Autodesk Fusion 360 part; units mm, degrees
(part 3 of 3)
sketch "Sketch14" plane through (608, 0, 0) normal (1, 0, 0) x (0, 0, -1) in component "ДСП 16 — ламель прямая 982х100х16 мм — 8 шт"
  line L0 (-270, 982) -> (-295, 982) construction
  line L1 (-295, 982) -> (-295, 0) construction
  line L2 (-295, 0) -> (-245, 0) construction
  line L3 (-245, 0) -> (-245, 16) construction
  line L4 (-245, 16) -> (-195, 16) construction
  line L5 (-195, 16) -> (-195, 245.5) construction
  line L6 (-195, 245.5) -> (-245, 245.5) construction
  line L7 (-245, 245.5) -> (-245, 261.5) construction
  line L8 (-245, 261.5) -> (-195, 261.5) construction
  line L9 (-195, 261.5) -> (-195, 491) construction
  line L10 (-195, 491) -> (-245, 491) construction
  line L11 (-245, 491) -> (-245, 507) construction
  line L12 (-245, 507) -> (-195, 507) construction
  line L13 (-195, 507) -> (-195, 736.5) construction
  line L14 (-195, 736.5) -> (-245, 736.5) construction
  line L15 (-245, 736.5) -> (-245, 752.5) construction
  line L16 (-245, 752.5) -> (-195, 752.5) construction
  line L17 (-195, 752.5) -> (-195, 850) construction
  line L18 (-195, 850) -> (-270, 850) construction
  line L19 (-270, 850) -> (-270, 982) construction
  line L20 (-245, -0.1) -> (-193, -0.1)
  line L21 (-193, -0.1) -> (-193, 16.1)
  line L22 (-193, 16.1) -> (-245, 16.1)
  line L23 (-245, 16.1) -> (-245, -0.1)
  line L24 (-245, 245.4) -> (-193, 245.4)
  line L25 (-193, 245.4) -> (-193, 261.6)
  line L26 (-193, 261.6) -> (-245, 261.6)
  line L27 (-245, 261.6) -> (-245, 245.4)
  line L28 (-245, 490.9) -> (-193, 490.9)
  line L29 (-193, 490.9) -> (-193, 507.1)
  line L30 (-193, 507.1) -> (-245, 507.1)
  line L31 (-245, 507.1) -> (-245, 490.9)
  line L32 (-245, 736.4) -> (-193, 736.4)
  line L33 (-193, 736.4) -> (-193, 752.6)
  line L34 (-193, 752.6) -> (-245, 752.6)
  line L35 (-245, 752.6) -> (-245, 736.4)
extrude "Зазор паза +0,2 мм Тело 12" cut sketch "Sketch14" along normal mid plane 80 bodies 45 in component "ДСП 16 — ламель прямая 982х100х16 мм — 8 шт"
sketch "Sketch15" plane through (592, 0, 0) normal (-1, 0, 0) x (0, 0, 1) in component "ДСП 16 — ламель прямая 982х100х16 мм — 8 шт"
  line L0 (195, 507.1) -> (245, 507.1) construction
  line L1 (245, 507.1) -> (245, 490.9) construction
  line L2 (245, 490.9) -> (195, 490.9) construction
  line L3 (195, 490.9) -> (195, 261.6) construction
  line L4 (195, 261.6) -> (245, 261.6) construction
  line L5 (245, 261.6) -> (245, 245.4) construction
  line L6 (245, 245.4) -> (195, 245.4) construction
  line L7 (195, 245.4) -> (195, 16.1) construction
  line L8 (195, 16.1) -> (245, 16.1) construction
  line L9 (245, 16.1) -> (245, 0) construction
  line L10 (245, 0) -> (295, 0) construction
  line L11 (295, 0) -> (295, 982) construction
  line L12 (295, 982) -> (270, 982) construction
  line L13 (270, 982) -> (270, 850) construction
  line L14 (270, 850) -> (195, 850) construction
  line L15 (195, 850) -> (195, 752.6) construction
  line L16 (195, 752.6) -> (245, 752.6) construction
  line L17 (245, 752.6) -> (245, 736.4) construction
  line L18 (245, 736.4) -> (195, 736.4) construction
  line L19 (195, 736.4) -> (195, 507.1) construction
  circle A0 centre (243.5151, 14.6151) radius 2.1
  circle A1 centre (243.5151, 246.8849) radius 2.1
  circle A2 centre (243.5151, 260.1151) radius 2.1
  circle A3 centre (243.5151, 492.3849) radius 2.1
  circle A4 centre (243.5151, 505.6151) radius 2.1
  circle A5 centre (243.5151, 737.8849) radius 2.1
  circle A6 centre (243.5151, 751.1151) radius 2.1
extrude "Догбон Ø4,2 мм Тело 12" cut sketch "Sketch15" along normal mid plane 80 bodies 45 in component "ДСП 16 — ламель прямая 982х100х16 мм — 8 шт"
sketch "Sketch16" plane through (808, 0, 0) normal (1, 0, 0) x (0, 0, -1) in component "ДСП 16 — ламель прямая 982х100х16 мм — 8 шт"
  line L0 (-270, 982) -> (-295, 982) construction
  line L1 (-295, 982) -> (-295, 0) construction
  line L2 (-295, 0) -> (-245, 0) construction
  line L3 (-245, 0) -> (-245, 16) construction
  line L4 (-245, 16) -> (-195, 16) construction
  line L5 (-195, 16) -> (-195, 245.5) construction
  line L6 (-195, 245.5) -> (-245, 245.5) construction
  line L7 (-245, 245.5) -> (-245, 261.5) construction
  line L8 (-245, 261.5) -> (-195, 261.5) construction
  line L9 (-195, 261.5) -> (-195, 491) construction
  line L10 (-195, 491) -> (-245, 491) construction
  line L11 (-245, 491) -> (-245, 507) construction
  line L12 (-245, 507) -> (-195, 507) construction
  line L13 (-195, 507) -> (-195, 736.5) construction
  line L14 (-195, 736.5) -> (-245, 736.5) construction
  line L15 (-245, 736.5) -> (-245, 752.5) construction
  line L16 (-245, 752.5) -> (-195, 752.5) construction
  line L17 (-195, 752.5) -> (-195, 850) construction
  line L18 (-195, 850) -> (-270, 850) construction
  line L19 (-270, 850) -> (-270, 982) construction
  line L20 (-245, -0.1) -> (-193, -0.1)
  line L21 (-193, -0.1) -> (-193, 16.1)
  line L22 (-193, 16.1) -> (-245, 16.1)
  line L23 (-245, 16.1) -> (-245, -0.1)
  line L24 (-245, 245.4) -> (-193, 245.4)
  line L25 (-193, 245.4) -> (-193, 261.6)
  line L26 (-193, 261.6) -> (-245, 261.6)
  line L27 (-245, 261.6) -> (-245, 245.4)
  line L28 (-245, 490.9) -> (-193, 490.9)
  line L29 (-193, 490.9) -> (-193, 507.1)
  line L30 (-193, 507.1) -> (-245, 507.1)
  line L31 (-245, 507.1) -> (-245, 490.9)
  line L32 (-245, 736.4) -> (-193, 736.4)
  line L33 (-193, 736.4) -> (-193, 752.6)
  line L34 (-193, 752.6) -> (-245, 752.6)
  line L35 (-245, 752.6) -> (-245, 736.4)
extrude "Зазор паза +0,2 мм Тело 14" cut sketch "Sketch16" along normal mid plane 80 bodies 47 in component "ДСП 16 — ламель прямая 982х100х16 мм — 8 шт"
sketch "Sketch17" plane through (792, 0, 0) normal (-1, 0, 0) x (0, 0, 1) in component "ДСП 16 — ламель прямая 982х100х16 мм — 8 шт"
  line L0 (195, 507.1) -> (245, 507.1) construction
  line L1 (245, 507.1) -> (245, 490.9) construction
  line L2 (245, 490.9) -> (195, 490.9) construction
  line L3 (195, 490.9) -> (195, 261.6) construction
  line L4 (195, 261.6) -> (245, 261.6) construction
  line L5 (245, 261.6) -> (245, 245.4) construction
  line L6 (245, 245.4) -> (195, 245.4) construction
  line L7 (195, 245.4) -> (195, 16.1) construction
  line L8 (195, 16.1) -> (245, 16.1) construction
  line L9 (245, 16.1) -> (245, 0) construction
  line L10 (245, 0) -> (295, 0) construction
  line L11 (295, 0) -> (295, 982) construction
  line L12 (295, 982) -> (270, 982) construction
  line L13 (270, 982) -> (270, 850) construction
  line L14 (270, 850) -> (195, 850) construction
  line L15 (195, 850) -> (195, 752.6) construction
  line L16 (195, 752.6) -> (245, 752.6) construction
  line L17 (245, 752.6) -> (245, 736.4) construction
  line L18 (245, 736.4) -> (195, 736.4) construction
  line L19 (195, 736.4) -> (195, 507.1) construction
  circle A0 centre (243.5151, 14.6151) radius 2.1
  circle A1 centre (243.5151, 246.8849) radius 2.1
  circle A2 centre (243.5151, 260.1151) radius 2.1
  circle A3 centre (243.5151, 492.3849) radius 2.1
  circle A4 centre (243.5151, 505.6151) radius 2.1
  circle A5 centre (243.5151, 737.8849) radius 2.1
  circle A6 centre (243.5151, 751.1151) radius 2.1
extrude "Догбон Ø4,2 мм Тело 14" cut sketch "Sketch17" along normal mid plane 80 bodies 47 in component "ДСП 16 — ламель прямая 982х100х16 мм — 8 шт"
sketch "Sketch2 (28)" plane through (695.5237, 0, 401.5608) normal (-0.866025, 0, -0.5) x (-0.5, 0, 0.866025) in component "ДСП 16 — ламель радиусная 982х100х16 мм — 6 шт"
  line L0 (-415.0962, 982) -> (-439.8753, 982) construction
  line L1 (-439.8753, 982) -> (-439.8753, 0) construction
  line L2 (-439.8753, 0) -> (-390.0962, 0) construction
  line L3 (-390.0962, 0) -> (-390.0962, 16) construction
  line L4 (-390.0962, 16) -> (-340.0962, 16) construction
  line L5 (-340.0962, 16) -> (-340.0962, 245.5) construction
  line L6 (-340.0962, 245.5) -> (-390.0962, 245.5) construction
  line L7 (-390.0962, 245.5) -> (-390.0962, 261.5) construction
  line L8 (-390.0962, 261.5) -> (-340.0962, 261.5) construction
  line L9 (-340.0962, 261.5) -> (-340.0962, 491) construction
  line L10 (-340.0962, 491) -> (-390.0962, 491) construction
  line L11 (-390.0962, 491) -> (-390.0962, 507) construction
  line L12 (-390.0962, 507) -> (-340.0962, 507) construction
  line L13 (-340.0962, 507) -> (-340.0962, 736.5) construction
  line L14 (-340.0962, 736.5) -> (-390.0962, 736.5) construction
  line L15 (-390.0962, 736.5) -> (-390.0962, 752.5) construction
  line L16 (-390.0962, 752.5) -> (-340.0962, 752.5) construction
  line L17 (-340.0962, 752.5) -> (-340.0962, 850) construction
  line L18 (-340.0962, 850) -> (-415.0962, 850) construction
  line L19 (-415.0962, 850) -> (-415.0962, 982) construction
  line L20 (-390.0962, -0.1) -> (-338.0962, -0.1)
  line L21 (-338.0962, -0.1) -> (-338.0962, 16.1)
  line L22 (-338.0962, 16.1) -> (-390.0962, 16.1)
  line L23 (-390.0962, 16.1) -> (-390.0962, -0.1)
  line L24 (-390.0962, 245.4) -> (-338.0962, 245.4)
  line L25 (-338.0962, 245.4) -> (-338.0962, 261.6)
  line L26 (-338.0962, 261.6) -> (-390.0962, 261.6)
  line L27 (-390.0962, 261.6) -> (-390.0962, 245.4)
  line L28 (-390.0962, 490.9) -> (-338.0962, 490.9)
  line L29 (-338.0962, 490.9) -> (-338.0962, 507.1)
  line L30 (-338.0962, 507.1) -> (-390.0962, 507.1)
  line L31 (-390.0962, 507.1) -> (-390.0962, 490.9)
  line L32 (-390.0962, 736.4) -> (-338.0962, 736.4)
  line L33 (-338.0962, 736.4) -> (-338.0962, 752.6)
  line L34 (-338.0962, 752.6) -> (-390.0962, 752.6)
  line L35 (-390.0962, 752.6) -> (-390.0962, 736.4)
extrude "Зазор паза +0,2 мм Тело 01'" cut sketch "Sketch2 (28)" along normal mid plane 80 bodies 48 in component "ДСП 16 — ламель радиусная 982х100х16 мм — 6 шт"
sketch "Sketch3 (8)" plane through (709.3801, 0, 409.5608) normal (0.866025, 0, 0.5) x (0.5, 0, -0.866025) in component "ДСП 16 — ламель радиусная 982х100х16 мм — 6 шт"
  line L0 (340.0962, 507.1) -> (390.0962, 507.1) construction
  line L1 (390.0962, 507.1) -> (390.0962, 490.9) construction
  line L2 (390.0962, 490.9) -> (340.0962, 490.9) construction
  line L3 (340.0962, 490.9) -> (340.0962, 261.6) construction
  line L4 (340.0962, 261.6) -> (390.0962, 261.6) construction
  line L5 (390.0962, 261.6) -> (390.0962, 245.4) construction
  line L6 (390.0962, 245.4) -> (340.0962, 245.4) construction
  line L7 (340.0962, 245.4) -> (340.0962, 16.1) construction
  line L8 (340.0962, 16.1) -> (390.0962, 16.1) construction
  line L9 (390.0962, 16.1) -> (390.0962, 0) construction
  line L10 (390.0962, 0) -> (439.8753, 0) construction
  line L11 (439.8753, 0) -> (439.8753, 982) construction
  line L12 (439.8753, 982) -> (415.0962, 982) construction
  line L13 (415.0962, 982) -> (415.0962, 850) construction
  line L14 (415.0962, 850) -> (340.0962, 850) construction
  line L15 (340.0962, 850) -> (340.0962, 752.6) construction
  line L16 (340.0962, 752.6) -> (390.0962, 752.6) construction
  line L17 (390.0962, 752.6) -> (390.0962, 736.4) construction
  line L18 (390.0962, 736.4) -> (340.0962, 736.4) construction
  line L19 (340.0962, 736.4) -> (340.0962, 507.1) construction
  circle A0 centre (388.6113, 14.6151) radius 2.1
  circle A1 centre (388.6113, 246.8849) radius 2.1
  circle A2 centre (388.6113, 260.1151) radius 2.1
  circle A3 centre (388.6113, 492.3849) radius 2.1
  circle A4 centre (388.6113, 505.6151) radius 2.1
  circle A5 centre (388.6113, 737.8849) radius 2.1
  circle A6 centre (388.6113, 751.1151) radius 2.1
extrude "Догбон Ø4,2 мм Тело 01'" cut sketch "Sketch3 (8)" along normal mid plane 80 bodies 48 in component "ДСП 16 — ламель радиусная 982х100х16 мм — 6 шт"
sketch "Sketch4 (2)" plane through (0, 0, 142) normal (0, 0, -1) x (-1, 0, 0) in component "ДСП 16 — ламель радиусная 982х100х16 мм — 6 шт"
  line L0 (-970, 982) -> (-994.7791, 982) construction
  line L1 (-994.7791, 982) -> (-994.7791, 0) construction
  line L2 (-994.7791, 0) -> (-945, 0) construction
  line L3 (-945, 0) -> (-945, 16) construction
  line L4 (-945, 16) -> (-895, 16) construction
  line L5 (-895, 16) -> (-895, 245.5) construction
  line L6 (-895, 245.5) -> (-945, 245.5) construction
  line L7 (-945, 245.5) -> (-945, 261.5) construction
  line L8 (-945, 261.5) -> (-895, 261.5) construction
  line L9 (-895, 261.5) -> (-895, 491) construction
  line L10 (-895, 491) -> (-945, 491) construction
  line L11 (-945, 491) -> (-945, 507) construction
  line L12 (-945, 507) -> (-895, 507) construction
  line L13 (-895, 507) -> (-895, 736.5) construction
  line L14 (-895, 736.5) -> (-945, 736.5) construction
  line L15 (-945, 736.5) -> (-945, 752.5) construction
  line L16 (-945, 752.5) -> (-895, 752.5) construction
  line L17 (-895, 752.5) -> (-895, 850) construction
  line L18 (-895, 850) -> (-970, 850) construction
  line L19 (-970, 850) -> (-970, 982) construction
  line L20 (-945, -0.1) -> (-893, -0.1)
  line L21 (-893, -0.1) -> (-893, 16.1)
  line L22 (-893, 16.1) -> (-945, 16.1)
  line L23 (-945, 16.1) -> (-945, -0.1)
  line L24 (-945, 245.4) -> (-893, 245.4)
  line L25 (-893, 245.4) -> (-893, 261.6)
  line L26 (-893, 261.6) -> (-945, 261.6)
  line L27 (-945, 261.6) -> (-945, 245.4)
  line L28 (-945, 490.9) -> (-893, 490.9)
  line L29 (-893, 490.9) -> (-893, 507.1)
  line L30 (-893, 507.1) -> (-945, 507.1)
  line L31 (-945, 507.1) -> (-945, 490.9)
  line L32 (-945, 736.4) -> (-893, 736.4)
  line L33 (-893, 736.4) -> (-893, 752.6)
  line L34 (-893, 752.6) -> (-945, 752.6)
  line L35 (-945, 752.6) -> (-945, 736.4)
extrude "Зазор паза +0,2 мм Тело 02" cut sketch "Sketch4 (2)" along normal mid plane 80 bodies 49 in component "ДСП 16 — ламель радиусная 982х100х16 мм — 6 шт"
sketch "Sketch5 (2)" plane through (0, 0, 158) normal (0, 0, 1) x (1, 0, 0) in component "ДСП 16 — ламель радиусная 982х100х16 мм — 6 шт"
  line L0 (895, 507.1) -> (945, 507.1) construction
  line L1 (945, 507.1) -> (945, 490.9) construction
  line L2 (945, 490.9) -> (895, 490.9) construction
  line L3 (895, 490.9) -> (895, 261.6) construction
  line L4 (895, 261.6) -> (945, 261.6) construction
  line L5 (945, 261.6) -> (945, 245.4) construction
  line L6 (945, 245.4) -> (895, 245.4) construction
  line L7 (895, 245.4) -> (895, 16.1) construction
  line L8 (895, 16.1) -> (945, 16.1) construction
  line L9 (945, 16.1) -> (945, 0) construction
  line L10 (945, 0) -> (994.7791, 0) construction
  line L11 (994.7791, 0) -> (994.7791, 982) construction
  line L12 (994.7791, 982) -> (970, 982) construction
  line L13 (970, 982) -> (970, 850) construction
  line L14 (970, 850) -> (895, 850) construction
  line L15 (895, 850) -> (895, 752.6) construction
  line L16 (895, 752.6) -> (945, 752.6) construction
  line L17 (945, 752.6) -> (945, 736.4) construction
  line L18 (945, 736.4) -> (895, 736.4) construction
  line L19 (895, 736.4) -> (895, 507.1) construction
  circle A0 centre (943.5151, 14.6151) radius 2.1
  circle A1 centre (943.5151, 246.8849) radius 2.1
  circle A2 centre (943.5151, 260.1151) radius 2.1
  circle A3 centre (943.5151, 492.3849) radius 2.1
  circle A4 centre (943.5151, 505.6151) radius 2.1
  circle A5 centre (943.5151, 737.8849) radius 2.1
  circle A6 centre (943.5151, 751.1151) radius 2.1
extrude "Догбон Ø4,2 мм Тело 02" cut sketch "Sketch5 (2)" along normal mid plane 80 bodies 49 in component "ДСП 16 — ламель радиусная 982х100х16 мм — 6 шт"
sketch "Sketch6 (2)" plane through (565.6199, 0, -326.5608) normal (-0.866025, 0, 0.5) x (0.5, 0, 0.866025) in component "ДСП 16 — ламель радиусная 982х100х16 мм — 6 шт"
  line L0 (699.683, 982) -> (674.9038, 982) construction
  line L1 (674.9038, 982) -> (674.9038, 850) construction
  line L2 (674.9038, 850) -> (599.9038, 850) construction
  line L3 (599.9038, 850) -> (599.9038, 752.5) construction
  line L4 (599.9038, 752.5) -> (649.9038, 752.5) construction
  line L5 (649.9038, 752.5) -> (649.9038, 736.5) construction
  line L6 (649.9038, 736.5) -> (599.9038, 736.5) construction
  line L7 (599.9038, 736.5) -> (599.9038, 507) construction
  line L8 (599.9038, 507) -> (649.9038, 507) construction
  line L9 (649.9038, 507) -> (649.9038, 491) construction
  line L10 (649.9038, 491) -> (599.9038, 491) construction
  line L11 (599.9038, 491) -> (599.9038, 261.5) construction
  line L12 (599.9038, 261.5) -> (649.9038, 261.5) construction
  line L13 (649.9038, 261.5) -> (649.9038, 245.5) construction
  line L14 (649.9038, 245.5) -> (599.9038, 245.5) construction
  line L15 (599.9038, 245.5) -> (599.9038, 16) construction
  line L16 (599.9038, 16) -> (649.9038, 16) construction
  line L17 (649.9038, 16) -> (649.9038, 0) construction
  line L18 (649.9038, 0) -> (699.683, 0) construction
  line L19 (699.683, 0) -> (699.683, 982) construction
  line L20 (649.9038, -0.1) -> (597.9038, -0.1)
  line L21 (597.9038, -0.1) -> (597.9038, 16.1)
  line L22 (597.9038, 16.1) -> (649.9038, 16.1)
  line L23 (649.9038, 16.1) -> (649.9038, -0.1)
  line L24 (649.9038, 245.4) -> (597.9038, 245.4)
  line L25 (597.9038, 245.4) -> (597.9038, 261.6)
  line L26 (597.9038, 261.6) -> (649.9038, 261.6)
  line L27 (649.9038, 261.6) -> (649.9038, 245.4)
  line L28 (649.9038, 490.9) -> (597.9038, 490.9)
  line L29 (597.9038, 490.9) -> (597.9038, 507.1)
  line L30 (597.9038, 507.1) -> (649.9038, 507.1)
  line L31 (649.9038, 507.1) -> (649.9038, 490.9)
  line L32 (649.9038, 736.4) -> (597.9038, 736.4)
  line L33 (597.9038, 736.4) -> (597.9038, 752.6)
  line L34 (597.9038, 752.6) -> (649.9038, 752.6)
  line L35 (649.9038, 752.6) -> (649.9038, 736.4)
extrude "Зазор паза +0,2 мм Тело 03'" cut sketch "Sketch6 (2)" along normal mid plane 80 bodies 50 in component "ДСП 16 — ламель радиусная 982х100х16 мм — 6 шт"
sketch "Sketch7 (2)" plane through (579.4763, 0, -334.5608) normal (0.866025, 0, -0.5) x (-0.5, 0, -0.866025) in component "ДСП 16 — ламель радиусная 982х100х16 мм — 6 шт"
  line L0 (-599.9038, 490.9) -> (-649.9038, 490.9) construction
  line L1 (-649.9038, 490.9) -> (-649.9038, 507.1) construction
  line L2 (-649.9038, 507.1) -> (-599.9038, 507.1) construction
  line L3 (-599.9038, 507.1) -> (-599.9038, 736.4) construction
  line L4 (-599.9038, 736.4) -> (-649.9038, 736.4) construction
  line L5 (-649.9038, 736.4) -> (-649.9038, 752.6) construction
  line L6 (-649.9038, 752.6) -> (-599.9038, 752.6) construction
  line L7 (-599.9038, 752.6) -> (-599.9038, 850) construction
  line L8 (-599.9038, 850) -> (-674.9038, 850) construction
  line L9 (-674.9038, 850) -> (-674.9038, 982) construction
  line L10 (-674.9038, 982) -> (-699.683, 982) construction
  line L11 (-699.683, 982) -> (-699.683, 0) construction
  line L12 (-699.683, 0) -> (-649.9038, 0) construction
  line L13 (-649.9038, 0) -> (-649.9038, 16.1) construction
  line L14 (-649.9038, 16.1) -> (-599.9038, 16.1) construction
  line L15 (-599.9038, 16.1) -> (-599.9038, 245.4) construction
  line L16 (-599.9038, 245.4) -> (-649.9038, 245.4) construction
  line L17 (-649.9038, 245.4) -> (-649.9038, 261.6) construction
  line L18 (-649.9038, 261.6) -> (-599.9038, 261.6) construction
  line L19 (-599.9038, 261.6) -> (-599.9038, 490.9) construction
  circle A0 centre (-648.4189, 14.6151) radius 2.1
  circle A1 centre (-648.4189, 246.8849) radius 2.1
  circle A2 centre (-648.4189, 260.1151) radius 2.1
  circle A3 centre (-648.4189, 492.3849) radius 2.1
  circle A4 centre (-648.4189, 505.6151) radius 2.1
  circle A5 centre (-648.4189, 737.8849) radius 2.1
  circle A6 centre (-648.4189, 751.1151) radius 2.1
extrude "Догбон Ø4,2 мм Тело 03'" cut sketch "Sketch7 (2)" along normal mid plane 80 bodies 50 in component "ДСП 16 — ламель радиусная 982х100х16 мм — 6 шт"
sketch "Sketch8 (2)" plane through (170.5237, 0, 98.4519) normal (-0.866025, 0, -0.5) x (-0.5, 0, 0.866025) in component "ДСП 16 — ламель радиусная 982х100х16 мм — 6 шт"
  line L0 (199.683, 982) -> (174.9038, 982) construction
  line L1 (174.9038, 982) -> (174.9038, 850) construction
  line L2 (174.9038, 850) -> (99.9038, 850) construction
  line L3 (99.9038, 850) -> (99.9038, 752.5) construction
  line L4 (99.9038, 752.5) -> (149.9038, 752.5) construction
  line L5 (149.9038, 752.5) -> (149.9038, 736.5) construction
  line L6 (149.9038, 736.5) -> (99.9038, 736.5) construction
  line L7 (99.9038, 736.5) -> (99.9038, 507) construction
  line L8 (99.9038, 507) -> (149.9038, 507) construction
  line L9 (149.9038, 507) -> (149.9038, 491) construction
  line L10 (149.9038, 491) -> (99.9038, 491) construction
  line L11 (99.9038, 491) -> (99.9038, 261.5) construction
  line L12 (99.9038, 261.5) -> (149.9038, 261.5) construction
  line L13 (149.9038, 261.5) -> (149.9038, 245.5) construction
  line L14 (149.9038, 245.5) -> (99.9038, 245.5) construction
  line L15 (99.9038, 245.5) -> (99.9038, 16) construction
  line L16 (99.9038, 16) -> (149.9038, 16) construction
  line L17 (149.9038, 16) -> (149.9038, 0) construction
  line L18 (149.9038, 0) -> (199.683, 0) construction
  line L19 (199.683, 0) -> (199.683, 982) construction
  line L20 (149.9038, -0.1) -> (97.9038, -0.1)
  line L21 (97.9038, -0.1) -> (97.9038, 16.1)
  line L22 (97.9038, 16.1) -> (149.9038, 16.1)
  line L23 (149.9038, 16.1) -> (149.9038, -0.1)
  line L24 (149.9038, 245.4) -> (97.9038, 245.4)
  line L25 (97.9038, 245.4) -> (97.9038, 261.6)
  line L26 (97.9038, 261.6) -> (149.9038, 261.6)
  line L27 (149.9038, 261.6) -> (149.9038, 245.4)
  line L28 (149.9038, 490.9) -> (97.9038, 490.9)
  line L29 (97.9038, 490.9) -> (97.9038, 507.1)
  line L30 (97.9038, 507.1) -> (149.9038, 507.1)
  line L31 (149.9038, 507.1) -> (149.9038, 490.9)
  line L32 (149.9038, 736.4) -> (97.9038, 736.4)
  line L33 (97.9038, 736.4) -> (97.9038, 752.6)
  line L34 (97.9038, 752.6) -> (149.9038, 752.6)
  line L35 (149.9038, 752.6) -> (149.9038, 736.4)
extrude "Зазор паза +0,2 мм Тело 04" cut sketch "Sketch8 (2)" along normal mid plane 80 bodies 51 in component "ДСП 16 — ламель радиусная 982х100х16 мм — 6 шт"
sketch "Sketch9 (2)" plane through (170.5237, 0, 98.4519) normal (-0.866025, 0, -0.5) x (-0.5, 0, 0.866025) in component "ДСП 16 — ламель радиусная 982х100х16 мм — 6 шт"
  line L0 (149.9038, 490.9) -> (99.9038, 490.9) construction
  line L1 (99.9038, 490.9) -> (99.9038, 261.6) construction
  line L2 (99.9038, 261.6) -> (149.9038, 261.6) construction
  line L3 (149.9038, 261.6) -> (149.9038, 245.4) construction
  line L4 (149.9038, 245.4) -> (99.9038, 245.4) construction
  line L5 (99.9038, 245.4) -> (99.9038, 16.1) construction
  line L6 (99.9038, 16.1) -> (149.9038, 16.1) construction
  line L7 (149.9038, 16.1) -> (149.9038, 0) construction
  line L8 (149.9038, 0) -> (199.683, 0) construction
  line L9 (199.683, 0) -> (199.683, 982) construction
  line L10 (199.683, 982) -> (174.9038, 982) construction
  line L11 (174.9038, 982) -> (174.9038, 850) construction
  line L12 (174.9038, 850) -> (99.9038, 850) construction
  line L13 (99.9038, 850) -> (99.9038, 752.6) construction
  line L14 (99.9038, 752.6) -> (149.9038, 752.6) construction
  line L15 (149.9038, 752.6) -> (149.9038, 736.4) construction
  line L16 (149.9038, 736.4) -> (99.9038, 736.4) construction
  line L17 (99.9038, 736.4) -> (99.9038, 507.1) construction
  line L18 (99.9038, 507.1) -> (149.9038, 507.1) construction
  line L19 (149.9038, 507.1) -> (149.9038, 490.9) construction
  circle A0 centre (148.4189, 14.6151) radius 2.1
  circle A1 centre (148.4189, 246.8849) radius 2.1
  circle A2 centre (148.4189, 260.1151) radius 2.1
  circle A3 centre (148.4189, 492.3849) radius 2.1
  circle A4 centre (148.4189, 505.6151) radius 2.1
  circle A5 centre (148.4189, 737.8849) radius 2.1
  circle A6 centre (148.4189, 751.1151) radius 2.1
extrude "Догбон Ø4,2 мм Тело 04" cut sketch "Sketch9 (2)" along normal mid plane 80 bodies 51 in component "ДСП 16 — ламель радиусная 982х100х16 мм — 6 шт"
sketch "Sketch10 (2)" plane through (0, 0, 158) normal (0, 0, 1) x (1, 0, 0) in component "ДСП 16 — ламель радиусная 982х100х16 мм — 6 шт"
  line L0 (30, 982) -> (5.2209, 982) construction
  line L1 (5.2209, 982) -> (5.2209, 0) construction
  line L2 (5.2209, 0) -> (55, 0) construction
  line L3 (55, 0) -> (55, 16) construction
  line L4 (55, 16) -> (105, 16) construction
  line L5 (105, 16) -> (105, 245.5) construction
  line L6 (105, 245.5) -> (55, 245.5) construction
  line L7 (55, 245.5) -> (55, 261.5) construction
  line L8 (55, 261.5) -> (105, 261.5) construction
  line L9 (105, 261.5) -> (105, 491) construction
  line L10 (105, 491) -> (55, 491) construction
  line L11 (55, 491) -> (55, 507) construction
  line L12 (55, 507) -> (105, 507) construction
  line L13 (105, 507) -> (105, 736.5) construction
  line L14 (105, 736.5) -> (55, 736.5) construction
  line L15 (55, 736.5) -> (55, 752.5) construction
  line L16 (55, 752.5) -> (105, 752.5) construction
  line L17 (105, 752.5) -> (105, 850) construction
  line L18 (105, 850) -> (30, 850) construction
  line L19 (30, 850) -> (30, 982) construction
  line L20 (55, -0.1) -> (107, -0.1)
  line L21 (107, -0.1) -> (107, 16.1)
  line L22 (107, 16.1) -> (55, 16.1)
  line L23 (55, 16.1) -> (55, -0.1)
  line L24 (55, 245.4) -> (107, 245.4)
  line L25 (107, 245.4) -> (107, 261.6)
  line L26 (107, 261.6) -> (55, 261.6)
  line L27 (55, 261.6) -> (55, 245.4)
  line L28 (55, 490.9) -> (107, 490.9)
  line L29 (107, 490.9) -> (107, 507.1)
  line L30 (107, 507.1) -> (55, 507.1)
  line L31 (55, 507.1) -> (55, 490.9)
  line L32 (55, 736.4) -> (107, 736.4)
  line L33 (107, 736.4) -> (107, 752.6)
  line L34 (107, 752.6) -> (55, 752.6)
  line L35 (55, 752.6) -> (55, 736.4)
extrude "Зазор паза +0,2 мм Тело 05'" cut sketch "Sketch10 (2)" along normal mid plane 80 bodies 52 in component "ДСП 16 — ламель радиусная 982х100х16 мм — 6 шт"
sketch "Sketch11 (2)" plane through (0, 0, 158) normal (0, 0, 1) x (1, 0, 0) in component "ДСП 16 — ламель радиусная 982х100х16 мм — 6 шт"
  line L0 (55, 507.1) -> (105, 507.1) construction
  line L1 (105, 507.1) -> (105, 736.4) construction
  line L2 (105, 736.4) -> (55, 736.4) construction
  line L3 (55, 736.4) -> (55, 752.6) construction
  line L4 (55, 752.6) -> (105, 752.6) construction
  line L5 (105, 752.6) -> (105, 850) construction
  line L6 (105, 850) -> (30, 850) construction
  line L7 (30, 850) -> (30, 982) construction
  line L8 (30, 982) -> (5.2209, 982) construction
  line L9 (5.2209, 982) -> (5.2209, 0) construction
  line L10 (5.2209, 0) -> (55, 0) construction
  line L11 (55, 0) -> (55, 16.1) construction
  line L12 (55, 16.1) -> (105, 16.1) construction
  line L13 (105, 16.1) -> (105, 245.4) construction
  line L14 (105, 245.4) -> (55, 245.4) construction
  line L15 (55, 245.4) -> (55, 261.6) construction
  line L16 (55, 261.6) -> (105, 261.6) construction
  line L17 (105, 261.6) -> (105, 490.9) construction
  line L18 (105, 490.9) -> (55, 490.9) construction
  line L19 (55, 490.9) -> (55, 507.1) construction
  circle A0 centre (56.4849, 14.6151) radius 2.1
  circle A1 centre (56.4849, 246.8849) radius 2.1
  circle A2 centre (56.4849, 260.1151) radius 2.1
  circle A3 centre (56.4849, 492.3849) radius 2.1
  circle A4 centre (56.4849, 505.6151) radius 2.1
  circle A5 centre (56.4849, 737.8849) radius 2.1
  circle A6 centre (56.4849, 751.1151) radius 2.1
extrude "Догбон Ø4,2 мм Тело 05'" cut sketch "Sketch11 (2)" along normal mid plane 80 bodies 52 in component "ДСП 16 — ламель радиусная 982х100х16 мм — 6 шт"
sketch "Sketch12 (2)" plane through (54.4763, 0, -31.4519) normal (0.866025, 0, -0.5) x (-0.5, 0, -0.866025) in component "ДСП 16 — ламель радиусная 982х100х16 мм — 6 шт"
  line L0 (-60.1247, 982) -> (-84.9038, 982) construction
  line L1 (-84.9038, 982) -> (-84.9038, 850) construction
  line L2 (-84.9038, 850) -> (-159.9038, 850) construction
  line L3 (-159.9038, 850) -> (-159.9038, 752.5) construction
  line L4 (-159.9038, 752.5) -> (-109.9038, 752.5) construction
  line L5 (-109.9038, 752.5) -> (-109.9038, 736.5) construction
  line L6 (-109.9038, 736.5) -> (-159.9038, 736.5) construction
  line L7 (-159.9038, 736.5) -> (-159.9038, 507) construction
  line L8 (-159.9038, 507) -> (-109.9038, 507) construction
  line L9 (-109.9038, 507) -> (-109.9038, 491) construction
  line L10 (-109.9038, 491) -> (-159.9038, 491) construction
  line L11 (-159.9038, 491) -> (-159.9038, 261.5) construction
  line L12 (-159.9038, 261.5) -> (-109.9038, 261.5) construction
  line L13 (-109.9038, 261.5) -> (-109.9038, 245.5) construction
  line L14 (-109.9038, 245.5) -> (-159.9038, 245.5) construction
  line L15 (-159.9038, 245.5) -> (-159.9038, 16) construction
  line L16 (-159.9038, 16) -> (-109.9038, 16) construction
  line L17 (-109.9038, 16) -> (-109.9038, 0) construction
  line L18 (-109.9038, 0) -> (-60.1247, 0) construction
  line L19 (-60.1247, 0) -> (-60.1247, 982) construction
  line L20 (-109.9038, -0.1) -> (-161.9038, -0.1)
  line L21 (-161.9038, -0.1) -> (-161.9038, 16.1)
  line L22 (-161.9038, 16.1) -> (-109.9038, 16.1)
  line L23 (-109.9038, 16.1) -> (-109.9038, -0.1)
  line L24 (-109.9038, 245.4) -> (-161.9038, 245.4)
  line L25 (-161.9038, 245.4) -> (-161.9038, 261.6)
  line L26 (-161.9038, 261.6) -> (-109.9038, 261.6)
  line L27 (-109.9038, 261.6) -> (-109.9038, 245.4)
  line L28 (-109.9038, 490.9) -> (-161.9038, 490.9)
  line L29 (-161.9038, 490.9) -> (-161.9038, 507.1)
  line L30 (-161.9038, 507.1) -> (-109.9038, 507.1)
  line L31 (-109.9038, 507.1) -> (-109.9038, 490.9)
  line L32 (-109.9038, 736.4) -> (-161.9038, 736.4)
  line L33 (-161.9038, 736.4) -> (-161.9038, 752.6)
  line L34 (-161.9038, 752.6) -> (-109.9038, 752.6)
  line L35 (-109.9038, 752.6) -> (-109.9038, 736.4)
extrude "Зазор паза +0,2 мм Тело 06" cut sketch "Sketch12 (2)" along normal mid plane 80 bodies 53 in component "ДСП 16 — ламель радиусная 982х100х16 мм — 6 шт"
sketch "Sketch13 (2)" plane through (40.6199, 0, -23.4519) normal (-0.866025, 0, 0.5) x (0.5, 0, 0.866025) in component "ДСП 16 — ламель радиусная 982х100х16 мм — 6 шт"
  line L0 (159.9038, 490.9) -> (109.9038, 490.9) construction
  line L1 (109.9038, 490.9) -> (109.9038, 507.1) construction
  line L2 (109.9038, 507.1) -> (159.9038, 507.1) construction
  line L3 (159.9038, 507.1) -> (159.9038, 736.4) construction
  line L4 (159.9038, 736.4) -> (109.9038, 736.4) construction
  line L5 (109.9038, 736.4) -> (109.9038, 752.6) construction
  line L6 (109.9038, 752.6) -> (159.9038, 752.6) construction
  line L7 (159.9038, 752.6) -> (159.9038, 850) construction
  line L8 (159.9038, 850) -> (84.9038, 850) construction
  line L9 (84.9038, 850) -> (84.9038, 982) construction
  line L10 (84.9038, 982) -> (60.1247, 982) construction
  line L11 (60.1247, 982) -> (60.1247, 0) construction
  line L12 (60.1247, 0) -> (109.9038, 0) construction
  line L13 (109.9038, 0) -> (109.9038, 16.1) construction
  line L14 (109.9038, 16.1) -> (159.9038, 16.1) construction
  line L15 (159.9038, 16.1) -> (159.9038, 245.4) construction
  line L16 (159.9038, 245.4) -> (109.9038, 245.4) construction
  line L17 (109.9038, 245.4) -> (109.9038, 261.6) construction
  line L18 (109.9038, 261.6) -> (159.9038, 261.6) construction
  line L19 (159.9038, 261.6) -> (159.9038, 490.9) construction
  circle A0 centre (111.3887, 14.6151) radius 2.1
  circle A1 centre (111.3887, 246.8849) radius 2.1
  circle A2 centre (111.3887, 260.1151) radius 2.1
  circle A3 centre (111.3887, 492.3849) radius 2.1
  circle A4 centre (111.3887, 505.6151) radius 2.1
  circle A5 centre (111.3887, 737.8849) radius 2.1
  circle A6 centre (111.3887, 751.1151) radius 2.1
extrude "Догбон Ø4,2 мм Тело 06" cut sketch "Sketch13 (2)" along normal mid plane 80 bodies 53 in component "ДСП 16 — ламель радиусная 982х100х16 мм — 6 шт"
ref_plane "WorkPlane2" through (0, 0, 0) normal (0, 0, 1) x (1, 0, 0) in component "ХДФ 3 — наружная обшивка — 2 шт"
sketch "Sketch2 (29)" plane through (0, 0, 0) normal (0, 0, 1) x (1, 0, 0) in component "ХДФ 3 — наружная обшивка — 2 шт"
  line L0 (396, 49.9) -> (404, 49.9)
  line L1 (404, 49.9) -> (404, 50)
  line L2 (404, 50) -> (396, 50)
  line L3 (396, 50) -> (396, 49.9)
  line L4 (396, 99.7) -> (404, 99.7)
  line L5 (404, 99.7) -> (404, 99.8)
  line L6 (404, 99.8) -> (396, 99.8)
  line L7 (396, 99.8) -> (396, 99.7)
  line L8 (396, 149.7) -> (404, 149.7)
  line L9 (404, 149.7) -> (404, 149.8)
  line L10 (404, 149.8) -> (396, 149.8)
  line L11 (396, 149.8) -> (396, 149.7)
  line L12 (396, 199.5) -> (404, 199.5)
  line L13 (404, 199.5) -> (404, 199.6)
  line L14 (404, 199.6) -> (396, 199.6)
  line L15 (396, 199.6) -> (396, 199.5)
  line L16 (396, 249.5) -> (404, 249.5)
  line L17 (404, 249.5) -> (404, 249.6)
  line L18 (404, 249.6) -> (396, 249.6)
  line L19 (396, 249.6) -> (396, 249.5)
  line L20 (396, 299.3) -> (404, 299.3)
  line L21 (404, 299.3) -> (404, 299.4)
  line L22 (404, 299.4) -> (396, 299.4)
  line L23 (396, 299.4) -> (396, 299.3)
  line L24 (396, 349.3) -> (404, 349.3)
  line L25 (404, 349.3) -> (404, 349.4)
  line L26 (404, 349.4) -> (396, 349.4)
  line L27 (396, 349.4) -> (396, 349.3)
  line L28 (396, 399.1) -> (404, 399.1)
  line L29 (404, 399.1) -> (404, 399.2)
  line L30 (404, 399.2) -> (396, 399.2)
  line L31 (396, 399.2) -> (396, 399.1)
  line L32 (396, 449.1) -> (404, 449.1)
  line L33 (404, 449.1) -> (404, 449.2)
  line L34 (404, 449.2) -> (396, 449.2)
  line L35 (396, 449.2) -> (396, 449.1)
  line L36 (396, 498.9) -> (404, 498.9)
  line L37 (404, 498.9) -> (404, 499)
  line L38 (404, 499) -> (396, 499)
  line L39 (396, 499) -> (396, 498.9)
  line L40 (396, 548.9) -> (404, 548.9)
  line L41 (404, 548.9) -> (404, 549)
  line L42 (404, 549) -> (396, 549)
  line L43 (396, 549) -> (396, 548.9)
  line L44 (396, 598.7) -> (404, 598.7)
  line L45 (404, 598.7) -> (404, 598.8)
  line L46 (404, 598.8) -> (396, 598.8)
  line L47 (396, 598.8) -> (396, 598.7)
  line L48 (396, 648.7) -> (404, 648.7)
  line L49 (404, 648.7) -> (404, 648.8)
  line L50 (404, 648.8) -> (396, 648.8)
  line L51 (396, 648.8) -> (396, 648.7)
  line L52 (396, 698.5) -> (404, 698.5)
  line L53 (404, 698.5) -> (404, 698.6)
  line L54 (404, 698.6) -> (396, 698.6)
  line L55 (396, 698.6) -> (396, 698.5)
  line L56 (396, 748.5) -> (404, 748.5)
  line L57 (404, 748.5) -> (404, 748.6)
  line L58 (404, 748.6) -> (396, 748.6)
  line L59 (396, 748.6) -> (396, 748.5)
  line L60 (396, 798.3) -> (404, 798.3)
  line L61 (404, 798.3) -> (404, 798.4)
  line L62 (404, 798.4) -> (396, 798.4)
  line L63 (396, 798.4) -> (396, 798.3)
  line L64 (396, 848.3) -> (404, 848.3)
  line L65 (404, 848.3) -> (404, 848.4)
  line L66 (404, 848.4) -> (396, 848.4)
  line L67 (396, 848.4) -> (396, 848.3)
  line L68 (396, 898.1) -> (404, 898.1)
  line L69 (404, 898.1) -> (404, 898.2)
  line L70 (404, 898.2) -> (396, 898.2)
  line L71 (396, 898.2) -> (396, 898.1)
  line L72 (396, 948.1) -> (404, 948.1)
  line L73 (404, 948.1) -> (404, 948.2)
  line L74 (404, 948.2) -> (396, 948.2)
  line L75 (396, 948.2) -> (396, 948.1)
extrude "Зазор в пазах ХДФ +0,2 мм" cut sketch "Sketch2 (29)" along normal blind 300 bodies 58 in component "ХДФ 3 — наружная обшивка — 2 шт"
sketch "Sketch3 (9)" plane through (0, 0, 0) normal (0, 0, 1) x (1, 0, 0) in component "ХДФ 3 — наружная обшивка — 2 шт"
  circle A0 centre (402.5151, 48.5151) radius 2.1
  circle A1 centre (402.5151, 101.1849) radius 2.1
  circle A2 centre (402.5151, 148.3151) radius 2.1
  circle A3 centre (402.5151, 200.9849) radius 2.1
  circle A4 centre (402.5151, 248.1151) radius 2.1
  circle A5 centre (402.5151, 300.7849) radius 2.1
  circle A6 centre (402.5151, 347.9151) radius 2.1
  circle A7 centre (402.5151, 400.5849) radius 2.1
  circle A8 centre (402.5151, 447.7151) radius 2.1
  circle A9 centre (402.5151, 500.3849) radius 2.1
  circle A10 centre (402.5151, 547.5151) radius 2.1
  circle A11 centre (402.5151, 600.1849) radius 2.1
  circle A12 centre (402.5151, 647.3151) radius 2.1
  circle A13 centre (402.5151, 699.9849) radius 2.1
  circle A14 centre (402.5151, 747.1151) radius 2.1
  circle A15 centre (402.5151, 799.7849) radius 2.1
  circle A16 centre (402.5151, 846.9151) radius 2.1
  circle A17 centre (402.5151, 899.5849) radius 2.1
  circle A18 centre (402.5151, 946.7151) radius 2.1
extrude "Компактные догбоны пазов ХДФ Ø4,2 мм" cut sketch "Sketch3 (9)" along normal blind 300 bodies 58 in component "ХДФ 3 — наружная обшивка — 2 шт"
move_face "Кольцо перекрывает торец внутреннего ХДФ" offset 3 4 faces at (383.3333, 999.3333, 30) (87.4278, 998.6667, 252.3949) (616.6667, 999.3333, 270) (939.9737, 999.3333, 70.5977) on bodies 9 in component "Полистирол 2 — верхнее кольцо"
ref_plane "WorkPlane1" through (0, 866, 0) normal (0, 1, 0) x (0, 0, 1) in component "ХДФ 3 — внутренняя обшивка ниши — 2 шт"
sketch "Sketch1 (36)" plane through (0, 866, 0) normal (0, 1, 0) x (1, 0, 0) in component "ХДФ 3 — внутренняя обшивка ниши — 2 шт"
  line L0 (150, -30) -> (850, -30)
  arc A0 (850, -270) -> (850, -30) centre (850, -150) ccw
  line L1 (850, -270) -> (150, -270)
  arc A1 (150, -30) -> (150, -270) centre (150, -150) ccw
  line L2 (150, -33) -> (850, -33)
  arc A2 (850, -267) -> (850, -33) centre (850, -150) ccw
  line L3 (850, -267) -> (150, -267)
  arc A3 (150, -33) -> (150, -267) centre (150, -150) ccw
extrude "ХДФ 3 мм по внутренней поверхности" add sketch "Sketch1 (36)" along normal blind 132 separate body makes body 59 in component "ХДФ 3 — внутренняя обшивка ниши — 2 шт"
ref_plane "WorkPlane1" through (0, 0, 0) normal (0, 0, 1) x (1, 0, 0) in component "Вспомогательный контур внутреннего ХДФ"
sketch "Sketch1 (37)" plane through (0, 0, 0) normal (0, 0, 1) x (1, 0, 0) in component "Вспомогательный контур внутреннего ХДФ"
  line L0 (-100, 800) -> (-100, 1050)
  line L1 (-100, 1050) -> (596, 1050)
  line L2 (596, 1050) -> (596, 954)
  line L3 (596, 954) -> (604, 954)
  line L4 (604, 954) -> (604, 910)
  line L5 (604, 910) -> (596, 910)
  line L6 (596, 910) -> (596, 800)
  line L7 (596, 800) -> (-100, 800)
extrude "Extrude1''" add sketch "Sketch1 (37)" along normal blind 300 separate body makes body 60 in component "Вспомогательный контур внутреннего ХДФ"
split "Стыки внутреннего ХДФ на ламелях — шип-паз" by bodies 60 bodies 59 makes body 61 at (912.5722, 910, 47.6051) in component "ХДФ 3 — внутренняя обшивка ниши — 2 шт"
ref_plane "WorkPlane2" through (0, 0, 0) normal (0, 0, 1) x (1, 0, 0) in component "ХДФ 3 — внутренняя обшивка ниши — 2 шт"
sketch "Sketch2 (30)" plane through (0, 0, 0) normal (0, 0, 1) x (1, 0, 0) in component "ХДФ 3 — внутренняя обшивка ниши — 2 шт"
  line L0 (596, 909.9) -> (604, 909.9)
  line L1 (604, 909.9) -> (604, 910)
  line L2 (604, 910) -> (596, 910)
  line L3 (596, 910) -> (596, 909.9)
  line L4 (596, 954) -> (604, 954)
  line L5 (604, 954) -> (604, 954.1)
  line L6 (604, 954.1) -> (596, 954.1)
  line L7 (596, 954.1) -> (596, 954)
extrude "Паз внутреннего ХДФ — зазор 0,2 мм" cut sketch "Sketch2 (30)" along normal blind 300 bodies 61 in component "ХДФ 3 — внутренняя обшивка ниши — 2 шт"
sketch "Sketch3 (10)" plane through (0, 0, 0) normal (0, 0, 1) x (1, 0, 0) in component "ХДФ 3 — внутренняя обшивка ниши — 2 шт"
  circle A0 centre (602.5151, 911.3849) radius 2.1
  circle A1 centre (602.5151, 952.6151) radius 2.1
extrude "Догбон внутреннего ХДФ Ø4,2 мм" cut sketch "Sketch3 (10)" along normal blind 300 bodies 61 in component "ХДФ 3 — внутренняя обшивка ниши — 2 шт"
copy_body "CutPasteBodies1'''" bodies 7 removing the originals makes body 62 in component "ХДФ 3 — наружный 1"
copy_body "CutPasteBodies1''''" bodies 58 removing the originals makes body 63 in component "ХДФ 3 — наружный 2"
copy_body "CutPasteBodies1'''''" bodies 59 removing the originals makes body 64 in component "ХДФ 3 — внутренний 1"
copy_body "CutPasteBodies1''''''" bodies 61 removing the originals makes body 65 in component "ХДФ 3 — внутренний 2"
component "Исходная болванка" placed x (1, 0, 0) y (0, 1, 0) z (0, 0, 1) at (0, 0, 0)
component "Кашпо — каркас и облицовка" placed x (1, 0, 0) y (0, 1, 0) z (0, 0, 1) at (0, 0, 0)
component "ДСП 16 — горизонталь 5" placed x (1, 0, 0) y (0, 1, 0) z (0, 0, 1) at (0, 0, 0) in component "Кашпо — каркас и облицовка"
component "Полистирол 2 — наружная обшивка — 2 шт" placed x (1, 0, 0) y (0, 1, 0) z (0, 0, 1) at (0, 0, 0) in component "Кашпо — каркас и облицовка"
component "Полистирол 2 — верхнее кольцо" placed x (1, 0, 0) y (0, 1, 0) z (0, 0, 1) at (0, 0, 0) in component "Кашпо — каркас и облицовка"
component "ДСП 16 — горизонтали с пазами 990х290х16 мм — 4 шт" placed x (1, 0, 0) y (0, 1, 0) z (0, 0, 1) at (0, 0, 0) in component "Кашпо — каркас и облицовка"
component "ДСП 16 — ламель прямая 982х100х16 мм — 8 шт" placed x (1, 0, 0) y (0, 1, 0) z (0, 0, 1) at (0, 0, 0) in component "Кашпо — каркас и облицовка"
component "ДСП 16 — ламель радиусная 982х100х16 мм — 6 шт" placed x (1, 0, 0) y (0, 1, 0) z (0, 0, 1) at (0, 0, 0) in component "Кашпо — каркас и облицовка"
component "Исходные эскизы и операции" placed x (1, 0, 0) y (0, 1, 0) z (0, 0, 1) at (0, 0, 0) in component "Кашпо — каркас и облицовка"
component "ДСП 16 — дно ниши 940х240х16 мм — 1 шт" placed x (1, 0, 0) y (0, 1, 0) z (0, 0, 1) at (0, 0, 0) in component "Кашпо — каркас и облицовка"
component "Вспомогательный контур стыка ХДФ" placed x (1, 0, 0) y (0, 1, 0) z (0, 0, 1) at (0, 0, 0) in component "Кашпо — каркас и облицовка"
component "Вспомогательный контур прямого стыка ХДФ" placed x (1, 0, 0) y (0, 1, 0) z (0, 0, 1) at (0, 0, 0) in component "Кашпо — каркас и облицовка"
component "Вспомогательный контур внутреннего ХДФ" placed x (1, 0, 0) y (0, 1, 0) z (0, 0, 1) at (0, 0, 0) in component "Кашпо — каркас и облицовка"
component "ХДФ 3 — наружный 1" placed x (1, 0, 0) y (0, 1, 0) z (0, 0, 1) at (0, 0, 0) in component "Кашпо — каркас и облицовка"
component "ХДФ 3 — наружный 2" placed x (1, 0, 0) y (0, 1, 0) z (0, 0, 1) at (0, 0, 0) in component "Кашпо — каркас и облицовка"
component "ХДФ 3 — внутренний 1" placed x (1, 0, 0) y (0, 1, 0) z (0, 0, 1) at (0, 0, 0) in component "Кашпо — каркас и облицовка"
component "ХДФ 3 — внутренний 2" placed x (1, 0, 0) y (0, 1, 0) z (0, 0, 1) at (0, 0, 0) in component "Кашпо — каркас и облицовка"
component "ДСП 16 — горизонталь 1" placed x (1, 0, 0) y (0, 1, 0) z (0, 0, 1) at (0, 0, 0) in component "Исходные эскизы и операции"
component "ДСП 16 — горизонталь 2" placed x (1, 0, 0) y (0, 1, 0) z (0, 0, 1) at (0, 0, 0) in component "Исходные эскизы и операции"
component "ДСП 16 — горизонталь 3" placed x (1, 0, 0) y (0, 1, 0) z (0, 0, 1) at (0, 0, 0) in component "Исходные эскизы и операции"
component "ДСП 16 — горизонталь 4" placed x (1, 0, 0) y (0, 1, 0) z (0, 0, 1) at (0, 0, 0) in component "Исходные эскизы и операции"
component "Ламель ДСП 16 — 01" placed x (0, 0, 1) y (0, 1, 0) z (-1, 0, 0) at (200, 0, 5) in component "Исходные эскизы и операции"
component "Ламель ДСП 16 — 02" placed x (0, 0, 1) y (0, 1, 0) z (-1, 0, 0) at (300, 0, 5) in component "Исходные эскизы и операции"
component "Ламель ДСП 16 — 03" placed x (0, 0, 1) y (0, 1, 0) z (-1, 0, 0) at (400, 0, 5) in component "Исходные эскизы и операции"
component "Ламель ДСП 16 — 04" placed x (0, 0, 1) y (0, 1, 0) z (-1, 0, 0) at (500, 0, 5) in component "Исходные эскизы и операции"
component "Ламель ДСП 16 — 05" placed x (0, 0, 1) y (0, 1, 0) z (-1, 0, 0) at (600, 0, 5) in component "Исходные эскизы и операции"
component "Ламель ДСП 16 — 06" placed x (0, 0, 1) y (0, 1, 0) z (-1, 0, 0) at (700, 0, 5) in component "Исходные эскизы и операции"
component "Ламель ДСП 16 — 07" placed x (0, 0, 1) y (0, 1, 0) z (-1, 0, 0) at (800, 0, 5) in component "Исходные эскизы и операции"
component "Ламель ДСП 16 — 08" placed x (0, 0, -1) y (0, 1, 0) z (1, 0, 0) at (200, 0, 295) in component "Исходные эскизы и операции"
component "Ламель ДСП 16 — 09" placed x (0, 0, -1) y (0, 1, 0) z (1, 0, 0) at (300, 0, 295) in component "Исходные эскизы и операции"
component "Ламель ДСП 16 — 10" placed x (0, 0, -1) y (0, 1, 0) z (1, 0, 0) at (400, 0, 295) in component "Исходные эскизы и операции"
component "Ламель ДСП 16 — 11" placed x (0, 0, -1) y (0, 1, 0) z (1, 0, 0) at (500, 0, 295) in component "Исходные эскизы и операции"
component "Ламель ДСП 16 — 12" placed x (0, 0, -1) y (0, 1, 0) z (1, 0, 0) at (600, 0, 295) in component "Исходные эскизы и операции"
component "Ламель ДСП 16 — 13" placed x (0, 0, -1) y (0, 1, 0) z (1, 0, 0) at (700, 0, 295) in component "Исходные эскизы и операции"
component "Ламель ДСП 16 — 14" placed x (0, 0, -1) y (0, 1, 0) z (1, 0, 0) at (800, 0, 295) in component "Исходные эскизы и операции"
component "Ламель ДСП 16 — 15" placed x (-0.5, 0, 0.866025) y (0, 1, 0) z (-0.866025, 0, -0.5) at (922.5, 0, 24.4263) in component "Исходные эскизы и операции"
component "Ламель ДСП 16 — 16" placed x (-1, 0, 0) y (0, 1, 0) z (0, 0, -1) at (995, 0, 150) in component "Исходные эскизы и операции"
component "Ламель ДСП 16 — 17" placed x (-0.5, 0, -0.866025) y (0, 1, 0) z (0.866025, 0, -0.5) at (922.5, 0, 275.5737) in component "Исходные эскизы и операции"
component "Ламель ДСП 16 — 18" placed x (0.5, 0, -0.866025) y (0, 1, 0) z (0.866025, 0, 0.5) at (77.5, 0, 275.5737) in component "Исходные эскизы и операции"
component "Ламель ДСП 16 — 19" placed x (1, 0, 0) y (0, 1, 0) z (0, 0, 1) at (5, 0, 150) in component "Исходные эскизы и операции"
component "Ламель ДСП 16 — 20" placed x (0.5, 0, 0.866025) y (0, 1, 0) z (-0.866025, 0, 0.5) at (77.5, 0, 24.4263) in component "Исходные эскизы и операции"
component "ХДФ 3 — наружная обшивка — 2 шт" placed x (1, 0, 0) y (0, 1, 0) z (0, 0, 1) at (0, 0, 0) in component "Исходные эскизы и операции"
component "ХДФ 3 — внутренняя обшивка ниши — 2 шт" placed x (1, 0, 0) y (0, 1, 0) z (0, 0, 1) at (0, 0, 0) in component "Исходные эскизы и операции"
named bodies: "ДСП 16 — горизонталь 1", "ДСП 16 — горизонталь 2", "ДСП 16 — горизонталь 3", "ДСП 16 — горизонталь 4", "ДСП 16 — горизонталь 5", "ХДФ 3 — часть 1", "Полистирол 2 — часть 1", "Полистирол 2 — верхнее кольцо", "Ламель ДСП 16 — 01", "Ламель ДСП 16 — 02", "Ламель ДСП 16 — 03", "Ламель ДСП 16 — 04", "Ламель ДСП 16 — 05", "Ламель ДСП 16 — 06", "Ламель ДСП 16 — 07", "Ламель ДСП 16 — 08", "Ламель ДСП 16 — 09", "Ламель ДСП 16 — 10", "Ламель ДСП 16 — 11", "Ламель ДСП 16 — 12", "Ламель ДСП 16 — 13", "Ламель ДСП 16 — 14", "Ламель ДСП 16 — 15", "Ламель ДСП 16 — 16", "Ламель ДСП 16 — 17", "Ламель ДСП 16 — 18", "Ламель ДСП 16 — 19", "Ламель ДСП 16 — 20", "Тело 01", "Тело 02", "Тело 03", "Тело 04", "Тело 05", "Тело 06", "Тело 07", "Тело 08", "Тело 09", "Тело 10", "Тело 11", "Тело 12", "Тело 13", "Тело 14", "Дно ниши", "ХДФ 3 — часть 2", "Полистирол 2 — часть 2", "ХДФ внутренний — часть 1 — шип", "ХДФ внутренний — часть 2 — паз"
